Autodesk Fusion 360 part; units mm, degrees
note: some values were not read from the file. Set by a fixed rule: which face or edge a step refers to.
(part 2 of 2)
sketch "Sketch2" plane through (-9.3104, 0, 0) normal (1, 0, 0) x (0, 1, 0)
  line L0 (-29.8542, 0) -> (11.1458, 0)
  line L1 (11.1458, 0) -> (11.1458, 240)
  line L2 (11.1458, 240) -> (-29.8542, 240)
  line L3 (-29.8542, 240) -> (-29.8542, 0)
  circle A0 centre (-21.8542, 179.6) radius 2
  circle A1 centre (-21.8542, 149.6) radius 2
  circle A2 centre (-1.8542, 179.6) radius 2
  circle A3 centre (-1.8542, 149.6) radius 2
  dimension "d5" = 4
  dimension "d6" = 4
  dimension "d7" = 30
  dimension "d8" = 8
  dimension "d9" = 8
  dimension "d10" = 4
  dimension "d11" = 4
  dimension "d12" = 20
  dimension "d13" = 60.4
  dimension "d14" = 60.4
  dimension "d15" = 28
  dimension "d16" = 30
  measures "d5" diameter of A0
  measures "d6" diameter of A1
  measures "d7" vertical distance of A0.centre A1.centre
  measures "d8" distance of L3 A0.centre
  measures "d9" distance of L3 A1.centre
  measures "d10" diameter of A2
  measures "d11" diameter of A3
  measures "d12" distance of A0.centre A2.centre
  measures "d13" distance of L2 A0.centre
  measures "d14" distance of L2 A2.centre
  measures "d15" distance of L3 A3.centre
  measures "d16" distance of A2.centre A3.centre
extrude "Extrude2" cut sketch "Sketch2" against normal blind 5 contours A0 | A1 | A2 | A3
equation "d7 = 26 mm + 4 mm"
equation "d13 = 44.5 mm - 2 mm + 11.9 mm + 6 mm"
equation "d14 = d13"
equation "d15 = 8 mm + 20 mm"

design "E-box"
part number: 2026-10-19-21-22-05-736
Autodesk Fusion 360 part; units mm, degrees
sketch "Sketch1" plane through (0, 0, 0) normal (0, 0, 1) x (1, 0, 0)
  line L0 (-27.5125, 15.5989) -> (97.4875, 15.5989)
  line L1 (97.4875, 15.5989) -> (97.4875, 115.5989)
  line L2 (97.4875, 115.5989) -> (-27.5125, 115.5989)
  line L3 (-27.5125, 115.5989) -> (-27.5125, 15.5989)
  line L4 (-22.2722, 112.09) -> (92.4875, 112.09)
  line L5 (92.4875, 112.09) -> (92.4875, 20)
  line L6 (92.4875, 20) -> (-22.2722, 20)
  line L7 (-22.2722, 20) -> (-22.2722, 112.09)
  dimension "d1" = 125
  dimension "d2" = 100
  dimension "d3" = 5
  constraint horizontal L0
  constraint vertical L1
  constraint horizontal L2
  constraint vertical L3
  constraint horizontal L4
  constraint vertical L5
  constraint horizontal L6
  constraint vertical L7
  measures "d1" distance of L0.start L0.end
  measures "d2" distance of L0.start L2.end
  measures "d3" distance of L1 L5
extrude "Extrude1" add sketch "Sketch1" along normal blind 10
extrude "Extrude2" add 1 faces at (-25.7658, 50.3992, 10) along direction (0, 0, 1) blind 90
extrude "Extrude3" cut 1 faces at (-25.7658, 50.3992, 100) along direction (0, 0, -1) blind 40
sketch "Sketch2" plane through (0, 0, 0) normal (0, 0, -1) x (1, 0, 0)
  line L0 (-22.2722, -20) -> (92.4875, -20)
  line L1 (92.4875, -20) -> (92.4875, -112.09)
  line L2 (92.4875, -112.09) -> (-22.2722, -112.09)
  line L3 (-22.2722, -112.09) -> (-22.2722, -20)
  line L4 (-27.5125, -15.5989) -> (-27.5125, -115.5989)
  line L5 (-27.5125, -115.5989) -> (97.4875, -115.5989)
  line L6 (97.4875, -115.5989) -> (97.4875, -15.5989)
  line L7 (97.4875, -15.5989) -> (-27.5125, -15.5989)
  line L8 (97.4875, -74.5989) -> (-27.5125, -74.5989)
  dimension "d10" = 41
  constraint coincident L6 L8.start
  constraint coincident L4 L8.end
  constraint perpendicular L4 L8
  measures "d10" distance of L5 L8
extrude "Extrude4" cut sketch "Sketch2" against normal blind 10 contours L1 L2 L3 L4 L5 L6 L8
sketch "Sketch3" plane through (92.4875, 0, 0) normal (-1, 0, 0) x (0, -1, 0)
  line L0 (-112.09, 10) -> (-74.5989, 10)
  line L1 (-74.5989, 10) -> (-74.5989, 0)
  line L2 (-74.5989, 0) -> (-20, 0)
  line L3 (-20, 0) -> (-20, 60)
  line L4 (-20, 60) -> (-112.09, 60)
  line L5 (-112.09, 60) -> (-112.09, 10)
  line L6 (-74.5989, 5) -> (-20, 5)
  constraint midpoint L1 L6.start
  constraint coincident L3 L6.end
  constraint perpendicular L3 L6
extrude "Extrude5" add sketch "Sketch3" along normal blind 115 contours L1 L2 L3 L6
sketch "Sketch4" plane through (0, 0, 60) normal (0, 0, 1) x (-1, 0, 0)
  line L0 (-92.4875, -20) -> (22.2722, -20)
  line L1 (22.2722, -20) -> (22.2722, -112.09)
  line L2 (22.2722, -112.09) -> (-92.4875, -112.09)
  line L3 (-92.4875, -112.09) -> (-92.4875, -20)
  line L4 (27.5125, -115.5989) -> (27.5125, -15.5989)
  line L5 (27.5125, -15.5989) -> (-97.4875, -15.5989)
  line L6 (-97.4875, -15.5989) -> (-97.4875, -115.5989)
  line L7 (-97.4875, -115.5989) -> (27.5125, -115.5989)
  line L8 (22.2722, -20) -> (27.5125, -20)
  line L9 (22.2722, -112.09) -> (27.5125, -112.09)
  constraint coincident L0.end L1.start
  constraint coincident L4 L8.end
  constraint perpendicular L4 L8
  constraint coincident L1.end L2.start
  constraint coincident L4 L9.end
  constraint perpendicular L4 L9
extrude "Extrude6" cut sketch "Sketch4" against normal blind 7 contours L1 L4 L8 L9
sketch "Sketch5" plane through (0, 20, 0) normal (0, 1, 0) x (-1, 0, 0)
  line L0 (-92.4875, 5) -> (22.2722, 5)
  line L1 (22.2722, 5) -> (22.2722, 53)
  line L2 (22.2722, 53) -> (27.5125, 53)
  line L3 (27.5125, 53) -> (27.5125, 60)
  line L4 (27.5125, 60) -> (-92.4875, 60)
  line L5 (-92.4875, 60) -> (-92.4875, 5)
  line L6 (-92.4875, 60) -> (24.7074, 60)
  line L7 (24.7074, 60) -> (24.7074, 57)
  line L8 (24.7074, 57) -> (-92.4875, 57)
  line L9 (-92.4875, 57) -> (-92.4875, 60)
  dimension "d17" = 3
  constraint horizontal L6
  constraint vertical L7
  constraint horizontal L8
  constraint vertical L9
  constraint coincident L4.end L5.start
  measures "d17" distance of L4.end L8.end
extrude "Extrude7" add sketch "Sketch5" along normal blind 2 contours L4 L5 L6 L7 L8 L9
sketch "Sketch6" plane through (0, 112.09, 0) normal (0, -1, 0) x (1, 0, 0)
  line L0 (-22.2722, 10) -> (92.4875, 10)
  line L1 (92.4875, 10) -> (92.4875, 60)
  line L2 (92.4875, 60) -> (-27.5125, 60)
  line L3 (-27.5125, 60) -> (-27.5125, 53)
  line L4 (-27.5125, 53) -> (-22.2722, 53)
  line L5 (-22.2722, 53) -> (-22.2722, 10)
  line L6 (-27.5125, 60) -> (92.4875, 60)
  line L7 (92.4875, 60) -> (92.4875, 57)
  line L8 (92.4875, 57) -> (-27.5125, 57)
  line L9 (-27.5125, 57) -> (-27.5125, 60)
  dimension "d20" = 3
  constraint horizontal L6
  constraint vertical L7
  constraint horizontal L8
  constraint vertical L9
  constraint coincident L2.end L3.start
  measures "d20" distance of L2.end L8.end
extrude "Extrude8" add sketch "Sketch6" along normal blind 2 contours L1 L2 L3 L6 L7 L8 L9
sketch "Sketch7" plane through (0, 112.09, 0) normal (0, -1, 0) x (1, 0, 0)
  line L0 (92.4875, 57) -> (-27.5125, 57)
  line L1 (-27.5125, 57) -> (-27.5125, 53)
  line L2 (-27.5125, 53) -> (-22.2722, 53)
  line L3 (-22.2722, 53) -> (-22.2722, 10)
  line L4 (-22.2722, 10) -> (92.4875, 10)
  line L5 (92.4875, 10) -> (92.4875, 57)
  line L6 (-22.2722, 53) -> (92.4875, 53)
  line L7 (92.4875, 53) -> (92.4875, 51)
  line L8 (92.4875, 51) -> (-22.2722, 51)
  line L9 (-22.2722, 51) -> (-22.2722, 53)
  dimension "d23" = 2
  constraint horizontal L6
  constraint vertical L7
  constraint horizontal L8
  constraint vertical L9
  constraint coincident L2.end L3.start
  measures "d23" distance of L2.end L8.end
extrude "Extrude9" add sketch "Sketch7" along normal blind 2 contours L3 L5 L6 L7 L8 L9
sketch "Sketch8" plane through (0, 20, 0) normal (0, 1, 0) x (-1, 0, 0)
  line L0 (24.7074, 60) -> (24.7074, 57)
  line L1 (24.7074, 57) -> (-92.4875, 57)
  line L2 (-92.4875, 57) -> (-92.4875, 5)
  line L3 (-92.4875, 5) -> (22.2722, 5)
  line L4 (22.2722, 5) -> (22.2722, 53)
  line L5 (22.2722, 53) -> (27.5125, 53)
  line L6 (27.5125, 53) -> (27.5125, 60)
  line L7 (27.5125, 60) -> (24.7074, 60)
  line L8 (22.2722, 53) -> (-92.4875, 53)
  line L9 (-92.4875, 53) -> (-92.4875, 51)
  line L10 (-92.4875, 51) -> (22.2722, 51)
  line L11 (22.2722, 51) -> (22.2722, 53)
  dimension "d26" = 2
  constraint horizontal L8
  constraint vertical L9
  constraint horizontal L10
  constraint vertical L11
  constraint coincident L4.end L5.start
  measures "d26" distance of L4.end L10.end
extrude "Extrude10" add sketch "Sketch8" along normal blind 2 contours L2 L4 L8 L9 L10 L11
sketch "Sketch9" plane through (0, 0, 53) normal (0, 0, 1) x (-1, 0, 0)
  line L0 (-92.4875, -112.09) -> (27.5125, -112.09)
  line L1 (27.5125, -112.09) -> (27.5125, -20)
  line L2 (27.5125, -20) -> (-92.4875, -20)
  line L3 (-92.4875, -20) -> (-92.4875, -22)
  line L4 (-92.4875, -22) -> (22.2722, -22)
  line L5 (22.2722, -22) -> (22.2722, -110.09)
  line L6 (22.2722, -110.09) -> (-92.4875, -110.09)
  line L7 (-92.4875, -110.09) -> (-92.4875, -112.09)
  line L8 (27.5125, -20) -> (22.2722, -20)
  line L9 (22.2722, -20) -> (22.2722, -112.09)
  line L10 (22.2722, -112.09) -> (27.5125, -112.09)
  line L11 (27.5125, -112.09) -> (27.5125, -20)
  constraint horizontal L8
  constraint vertical L9
  constraint horizontal L10
  constraint vertical L11
  constraint coincident L0 L9.end
  constraint coincident L1.end L2.start
extrude "Extrude11" add sketch "Sketch9" along normal blind 7 contours L0 L1 L2 L5 L8 L9 L10 L11
sketch "Sketch10" plane through (0, 0, 60) normal (0, 0, 1) x (-1, 0, 0)
  line L0 (22.2722, -110.09) -> (-92.4875, -110.09)
  line L1 (-92.4875, -110.09) -> (-92.4875, -22)
  line L2 (-92.4875, -22) -> (22.2722, -22)
  line L3 (22.2722, -22) -> (22.2722, -110.09)
  line L4 (27.5125, -115.5989) -> (27.5125, -15.5989)
  line L5 (27.5125, -15.5989) -> (-97.4875, -15.5989)
  line L6 (-97.4875, -15.5989) -> (-97.4875, -115.5989)
  line L7 (-97.4875, -115.5989) -> (27.5125, -115.5989)
  line L8 (-92.4875, -110.09) -> (-97.4875, -110.09)
  line L9 (-97.4875, -110.09) -> (-97.4875, -22)
  line L10 (-97.4875, -22) -> (-92.4875, -22)
  line L11 (-92.4875, -22) -> (-92.4875, -110.09)
  constraint horizontal L8
  constraint vertical L9
  constraint horizontal L10
  constraint vertical L11
  constraint coincident L6 L9.end
  constraint coincident L0.end L1.start
extrude "Extrude12" cut sketch "Sketch10" against normal blind 7 contours L1 L6 L8 L9 L10 L11
extrude "Extrude13" cut 1 faces at (92.4875, 111.4234, 54.3333) along direction (1, 0, 0) blind 20
extrude "Extrude14" cut 1 faces at (92.4875, 21.3333, 54.3333) along direction (1, 0, 0) blind 40
fillet "Fillet1" radius 2 3 edges at (34.9875, 15.5989, 60) (-27.5125, 65.5989, 60) (34.9875, 115.5989, 60)
fillet "Fillet2" radius 2 10 edges at (97.4875, 15.5989, 29) (97.4875, 16.1846, 59.4142) (97.4875, 19.7994, 60) (-27.5125, 15.5989, 29) (-26.9267, 16.1846, 59.4142) (-27.5125, 115.5989, 34) (-26.9267, 115.0131, 59.4142) (97.4875, 115.5989, 34) (97.4875, 115.0131, 59.4142) (97.4875, 111.8444, 60)
sketch "Sketch11" plane through (0, 20, 0) normal (0, 1, 0) x (-1, 0, 0)
  line L0 (22.2722, 51) -> (-92.4875, 51)
  line L1 (-92.4875, 51) -> (-92.4875, 5)
  line L2 (-92.4875, 5) -> (22.2722, 5)
  line L3 (22.2722, 5) -> (22.2722, 51)
  line L4 (13.7722, 5) -> (3.7722, 5)
  line L5 (3.7722, 5) -> (3.7722, 10)
  line L6 (3.7722, 10) -> (13.7722, 10)
  line L7 (13.7722, 10) -> (13.7722, 5)
  dimension "d41" = 10
  dimension "d42" = 5
  dimension "d43" = 8.5
  constraint horizontal L4
  constraint vertical L5
  constraint horizontal L6
  constraint vertical L7
  constraint coincident L2 L4.start
  measures "d41" distance of L4.start L4.end
  measures "d42" distance of L4.start L6.end
  measures "d43" distance of L3 L7
extrude "Extrude15" cut sketch "Sketch11" against normal blind 19 contours L2 L4 L5 L6 L7

design "Rod Holder (Front Part)"
part number: 2026-10-13-13-00-43-500
Autodesk Fusion 360 part; units mm, degrees
sketch "Sketch1" plane through (0, 0, 0) normal (0, 0, 1) x (1, 0, 0)
  line L0 (-14.2666, 6.6875) -> (165.7334, 6.6875)
  line L1 (165.7334, 6.6875) -> (165.7334, -13.3125)
  line L2 (165.7334, -13.3125) -> (-14.2666, -13.3125)
  line L3 (-14.2666, -13.3125) -> (-14.2666, 6.6875)
  dimension "d1" = 180
  dimension "d2" = 20
  constraint horizontal L0
  constraint vertical L1
  constraint horizontal L2
  constraint vertical L3
  measures "d1" distance of L0.start L0.end
  measures "d2" distance of L0.start L2.end
extrude "Extrude1" add sketch "Sketch1" along normal blind 55
sketch "Sketch2" plane through (0, 6.6875, 0) normal (0, 1, 0) x (-1, 0, 0)
  line L0 (-165.7334, 0) -> (14.2666, 0)
  line L1 (14.2666, 0) -> (14.2666, 55)
  line L2 (14.2666, 55) -> (-165.7334, 55)
  line L3 (-165.7334, 55) -> (-165.7334, 0)
  line L4 (-85.2334, 55) -> (-66.2334, 55)
  line L5 (-66.2334, 55) -> (-66.2334, 0)
  line L6 (-66.2334, 0) -> (-85.2334, 0)
  line L7 (-85.2334, 0) -> (-85.2334, 55)
  dimension "d5" = 19
  dimension "d6" = 80.5
  dimension "d7" = 80.5
  constraint horizontal L4
  constraint vertical L5
  constraint horizontal L6
  constraint vertical L7
  constraint coincident L2 L4.start
  measures "d5" distance of L4.start L4.end
  measures "d6" distance of L1 L5
  measures "d7" distance of L3 L7
extrude "Extrude2" cut sketch "Sketch2" against normal blind 5 contours L0 L2 L4 L5 L6 L7
sketch "Sketch3" plane through (0, 6.6875, 0) normal (0, 1, 0) x (-1, 0, 0)
  line L0 (-66.2334, 55) -> (-66.2334, 0)
  line L1 (-66.2334, 0) -> (14.2666, 0)
  line L2 (14.2666, 0) -> (14.2666, 55)
  line L3 (14.2666, 55) -> (-66.2334, 55)
  circle A0 centre (-21.7334, 43) radius 4
  dimension "d10" = 8
  dimension "d11" = 43
  dimension "d12" = 36
  measures "d10" diameter of A0
  measures "d11" distance of L1 A0.centre
  measures "d12" distance of L2 A0.centre
extrude "Extrude3" cut sketch "Sketch3" against normal blind 100 contours A0
sketch "Sketch4" plane through (0, 6.6875, 0) normal (0, 1, 0) x (-1, 0, 0)
  line L0 (-85.2334, 0) -> (-85.2334, 55)
  line L1 (-85.2334, 55) -> (-165.7334, 55)
  line L2 (-165.7334, 55) -> (-165.7334, 0)
  line L3 (-165.7334, 0) -> (-85.2334, 0)
  circle A0 centre (-129.7334, 43) radius 4
  dimension "d15" = 8
  dimension "d16" = 43
  dimension "d17" = 36
  measures "d15" diameter of A0
  measures "d16" distance of L3 A0.centre
  measures "d17" distance of L2 A0.centre
extrude "Extrude4" cut sketch "Sketch4" against normal blind 20 contours A0
fillet "Fillet1" chord length 10 1 edges at (165.7334, -3.3125, 55)
fillet "Fillet2" chord length 10 1 edges at (-14.2666, -3.3125, 55)
sketch "Sketch5" plane through (0, 1.6875, 0) normal (0, 1, 0) x (-1, 0, 0)
  line L0 (-85.2334, 0) -> (-66.2334, 0)
  line L1 (-66.2334, 0) -> (-66.2334, 55)
  line L2 (-66.2334, 55) -> (-85.2334, 55)
  line L3 (-85.2334, 55) -> (-85.2334, 0)
  line L4 (-85.2334, 55) -> (-66.2334, 55)
  line L5 (-66.2334, 55) -> (-66.2334, 41)
  line L6 (-66.2334, 41) -> (-85.2334, 41)
  line L7 (-85.2334, 41) -> (-85.2334, 55)
  dimension "d24" = 14
  constraint horizontal L4
  constraint vertical L5
  constraint horizontal L6
  constraint vertical L7
  constraint coincident L2.end L3.start
  measures "d24" distance of L2.end L6.end
extrude "Extrude5" add sketch "Sketch5" along normal blind 5 contours L1 L2 L3 L4 L5 L6 L7
sketch "Sketch6" plane through (0, 0, 55) normal (0, 0, 1) x (-1, 0, 0)
  line L0 (7.1956, 13.3125) -> (7.1956, -6.6875)
  line L1 (7.1956, 13.3125) -> (-158.6623, 13.3125)
  line L2 (-158.6623, -6.6875) -> (-158.6623, 13.3125)
  line L3 (-158.6623, -6.6875) -> (7.1956, -6.6875)
  line L4 (-67.8201, 2.2173) -> (-37.8201, 2.2173)
  line L5 (-37.8201, 2.2173) -> (-37.8201, 10.4173)
  line L6 (-37.8201, 10.4173) -> (-67.8201, 10.4173)
  line L7 (-67.8201, 10.4173) -> (-67.8201, 2.2173)
  dimension "d27" = 30
  dimension "d28" = 8.2
  constraint horizontal L4
  constraint vertical L5
  constraint horizontal L6
  constraint vertical L7
  measures "d27" distance of L4.start L4.end
  measures "d28" distance of L4.start L6.end
extrude "Extrude6" cut sketch "Sketch6" against normal blind 30 contours L4 L5 L6 L7
sketch "Sketch7" plane through (0, 6.6875, 0) normal (0, 1, 0) x (-1, 0, 0)
  circle A0 centre (-21.7334, 43) radius 4
  spline S0 degree 3 poles (-165.7334, 47.9289) (-165.7334, 48.8626) (-165.5484, 49.7871) (-164.8258, 51.5212) (-164.2911, 52.3119) (-162.9686, 53.6106) (-162.2037, 54.1163) (-160.5074, 54.8177) (-159.5893, 55) (-158.6623, 55) knots 0 0 0 0 0.280098 0.280098 0.563604 0.563604 0.836161 0.836161 1.114279 1.114279 1.114279 1.114279
  line L0 (-165.7334, 47.9289) -> (-165.7334, 0)
  line L1 (-165.7334, 0) -> (-85.2334, 0)
  line L2 (-85.2334, 0) -> (-85.2334, 41)
  line L3 (-85.2334, 41) -> (-66.2334, 41)
  line L4 (-66.2334, 41) -> (-66.2334, 0)
  line L5 (-66.2334, 0) -> (14.2666, 0)
  line L6 (14.2666, 0) -> (14.2666, 47.9289)
  spline S1 degree 3 poles (7.1956, 55) (8.1292, 55) (9.0537, 54.8151) (10.7879, 54.0924) (11.5785, 53.5577) (12.8772, 52.2352) (13.383, 51.4704) (14.0843, 49.7741) (14.2666, 48.856) (14.2666, 47.9289) knots 0 0 0 0 0.280098 0.280098 0.563604 0.563604 0.836161 0.836161 1.114279 1.114279 1.114279 1.114279
  line L7 (7.1956, 55) -> (-158.6623, 55)
  circle A1 centre (-129.7334, 43) radius 4
  line L8 (-65.7334, 37) -> (-45.7334, 37)
  line L9 (-45.7334, 37) -> (-45.7334, 25)
  line L10 (-45.7334, 25) -> (-65.7334, 25)
  line L11 (-65.7334, 25) -> (-65.7334, 37)
  dimension "d33" = 12
  dimension "d54" = 0.5
  constraint horizontal L8
  constraint vertical L9
  constraint horizontal L10
  constraint vertical L11
  measures "d33" distance of L8 L10
  measures "d54" distance of L4 L11
extrude "Extrude7" cut sketch "Sketch7" against normal blind 25 contours L8 L9 L10 L11
sketch "Sketch8" plane through (0, 0, 25) normal (0, 0, 1) x (-1, 0, 0)
  line L0 (-65.7334, 10.4173) -> (-67.8201, 10.4173)
  line L1 (-67.8201, 10.4173) -> (-67.8201, 2.2173)
  line L2 (-67.8201, 2.2173) -> (-65.7334, 2.2173)
  line L3 (-65.7334, 2.2173) -> (-65.7334, -6.6875)
  line L4 (-65.7334, -6.6875) -> (-45.7334, -6.6875)
  line L5 (-45.7334, -6.6875) -> (-45.7334, 2.2173)
  line L6 (-45.7334, 2.2173) -> (-37.8201, 2.2173)
  line L7 (-37.8201, 2.2173) -> (-37.8201, 10.4173)
  line L8 (-37.8201, 10.4173) -> (-45.7334, 10.4173)
  line L9 (-45.7334, 10.4173) -> (-45.7334, 13.3125)
  line L10 (-45.7334, 13.3125) -> (-65.7334, 13.3125)
  line L11 (-65.7334, 13.3125) -> (-65.7334, 10.4173)
  line L12 (-67.8201, 2.2173) -> (-65.7334, 2.2173)
  line L13 (-65.7334, 2.2173) -> (-65.7334, 10.4173)
  line L14 (-65.7334, 10.4173) -> (-67.8201, 10.4173)
  line L15 (-67.8201, 10.4173) -> (-67.8201, 2.2173)
  line L16 (-37.8201, 10.4173) -> (-45.7334, 10.4173)
  line L17 (-45.7334, 10.4173) -> (-45.7334, 2.2173)
  line L18 (-45.7334, 2.2173) -> (-37.8201, 2.2173)
  line L19 (-37.8201, 2.2173) -> (-37.8201, 10.4173)
  constraint horizontal L12
  constraint vertical L13
  constraint horizontal L14
  constraint vertical L15
  constraint coincident L0.start L11.end
  constraint coincident L1.end L2.start
  constraint horizontal L16
  constraint vertical L17
  constraint horizontal L18
  constraint vertical L19
  constraint coincident L5.end L6.start
  constraint coincident L7.end L8.start
extrude "Extrude8" add sketch "Sketch8" along normal blind 5 contours L0 L1 L2 L12 L13 L14 L15 | L6 L7 L8 L16 L17 L18 L19
sketch "Sketch9" plane through (65.7334, 0, 0) normal (-1, 0, 0) x (0, -1, 0)
  line L0 (-6.6875, 25) -> (13.3125, 25)
  line L1 (13.3125, 25) -> (13.3125, 37)
  line L2 (13.3125, 37) -> (10.4173, 37)
  line L3 (10.4173, 37) -> (10.4173, 30)
  line L4 (10.4173, 30) -> (2.2173, 30)
  line L5 (2.2173, 30) -> (2.2173, 37)
  line L6 (2.2173, 37) -> (-6.6875, 37)
  line L7 (-6.6875, 37) -> (-6.6875, 25)
  circle A0 centre (6.3173, 32.4309) radius 4
  dimension "d36" = 8
  measures "d36" diameter of A0
extrude "Extrude9" cut sketch "Sketch9" against normal blind 7.82 contours L4 A0 picked at (7.2516, 29.8591)
extrude "Extrude10" cut sketch "Sketch9" against normal blind 7.82 contours L4 A0 picked at (7.2516, 29.8591)
extrude "Extrude11" cut sketch "Sketch9" along normal blind 22.18 contours L4 A0 picked at (7.2516, 29.8591)
sketch "Sketch10" plane through (0, 6.6875, 0) normal (0, 1, 0) x (-1, 0, 0)
  line L0 (-45.7334, 37) -> (-45.7334, 25)
  line L1 (-45.7334, 25) -> (-65.7334, 25)
  line L2 (-65.7334, 25) -> (-65.7334, 37)
  line L3 (-65.7334, 37) -> (-45.7334, 37)
  circle A0 centre (-21.7334, 43) radius 4
  spline S0 degree 3 poles (-165.7334, 47.9289) (-165.7334, 48.8626) (-165.5484, 49.7871) (-164.8258, 51.5212) (-164.2911, 52.3119) (-162.9686, 53.6106) (-162.2037, 54.1163) (-160.5074, 54.8177) (-159.5893, 55) (-158.6623, 55) knots 0 0 0 0 0.280098 0.280098 0.563604 0.563604 0.836161 0.836161 1.114279 1.114279 1.114279 1.114279
  line L4 (-165.7334, 47.9289) -> (-165.7334, 0)
  line L5 (-165.7334, 0) -> (-85.2334, 0)
  line L6 (-85.2334, 0) -> (-85.2334, 41)
  line L7 (-85.2334, 41) -> (-66.2334, 41)
  line L8 (-66.2334, 41) -> (-66.2334, 0)
  line L9 (-66.2334, 0) -> (14.2666, 0)
  line L10 (14.2666, 0) -> (14.2666, 47.9289)
  spline S1 degree 3 poles (7.1956, 55) (8.1292, 55) (9.0537, 54.8151) (10.7879, 54.0924) (11.5785, 53.5577) (12.8772, 52.2352) (13.383, 51.4704) (14.0843, 49.7741) (14.2666, 48.856) (14.2666, 47.9289) knots 0 0 0 0 0.280098 0.280098 0.563604 0.563604 0.836161 0.836161 1.114279 1.114279 1.114279 1.114279
  line L11 (7.1956, 55) -> (-158.6623, 55)
  circle A1 centre (-129.7334, 43) radius 4
  line L12 (-65.7334, 37) -> (-40, 37)
  line L13 (-40, 37) -> (-40, 42)
  line L14 (-40, 42) -> (-65.7334, 42)
  line L15 (-65.7334, 42) -> (-65.7334, 37)
  constraint horizontal L12
  constraint vertical L13
  constraint horizontal L14
  constraint vertical L15
  constraint coincident L2.end L3.start
extrude "Extrude12" cut sketch "Sketch10" against normal blind 11 contours L3 L12 L13 L14 L15
sketch "Sketch11" plane through (0, 0, 25) normal (0, 0, 1) x (-1, 0, 0)
  line L0 (-65.7334, 13.3125) -> (-65.7334, -6.6875)
  line L1 (-65.7334, -6.6875) -> (-45.7334, -6.6875)
  line L2 (-45.7334, -6.6875) -> (-45.7334, 13.3125)
  line L3 (-45.7334, 13.3125) -> (-65.7334, 13.3125)
  line L4 (-65.7334, 0.7071) -> (-45.7334, 0.7071)
  line L5 (-45.7334, 0.7071) -> (-45.7334, -6.6875)
  line L6 (-45.7334, -6.6875) -> (-65.7334, -6.6875)
  line L7 (-65.7334, -6.6875) -> (-65.7334, 0.7071)
  constraint horizontal L4
  constraint vertical L5
  constraint horizontal L6
  constraint vertical L7
  constraint coincident L1.end L2.start
  constraint coincident L0 L4.start
extrude "Extrude13" add sketch "Sketch11" along normal blind 2 contours L0 L1 L2 L4 L5 L6 L7
chamfer "Chamfer1" distance 5 angle 45 1 edges at (65.7334, 2.2351, 42) tangent chain off
chamfer "Chamfer2" distance 5 angle 45 1 edges at (40, 2.2351, 42) tangent chain off
fillet "Fillet3" radius 1.5 1 edges at (65.7334, 2.9902, 27)
fillet "Fillet4" radius 1.5 1 edges at (45.7334, 2.9902, 27)
sketch "Sketch12" plane through (0, 6.6875, 0) normal (0, 1, 0) x (-1, 0, 0)
  line L0 (-40, 37) -> (-45.7334, 37)
  line L1 (-45.7334, 37) -> (-45.7334, 28.5)
  arc A0 (-47.2334, 27) -> (-45.7334, 28.5) centre (-47.2334, 28.5) ccw
  line L2 (-47.2334, 27) -> (-64.2334, 27)
  arc A1 (-65.7334, 28.5) -> (-64.2334, 27) centre (-64.2334, 28.5) ccw
  line L3 (-65.7334, 28.5) -> (-65.7334, 37)
  line L4 (-65.7334, 37) -> (-60.7334, 42)
  line L5 (-60.7334, 42) -> (-45, 42)
  line L6 (-45, 42) -> (-40, 37)
  circle A2 centre (-21.7334, 43) radius 4
  spline S0 degree 3 poles (-165.7334, 47.9289) (-165.7334, 48.8626) (-165.5484, 49.7871) (-164.8258, 51.5212) (-164.2911, 52.3119) (-162.9686, 53.6106) (-162.2037, 54.1163) (-160.5074, 54.8177) (-159.5893, 55) (-158.6623, 55) knots 0 0 0 0 0.280098 0.280098 0.563604 0.563604 0.836161 0.836161 1.114279 1.114279 1.114279 1.114279
  line L7 (-165.7334, 47.9289) -> (-165.7334, 0)
  line L8 (-165.7334, 0) -> (-85.2334, 0)
  line L9 (-85.2334, 0) -> (-85.2334, 41)
  line L10 (-85.2334, 41) -> (-66.2334, 41)
  line L11 (-66.2334, 41) -> (-66.2334, 0)
  line L12 (-66.2334, 0) -> (14.2666, 0)
  line L13 (14.2666, 0) -> (14.2666, 47.9289)
  spline S1 degree 3 poles (7.1956, 55) (8.1292, 55) (9.0537, 54.8151) (10.7879, 54.0924) (11.5785, 53.5577) (12.8772, 52.2352) (13.383, 51.4704) (14.0843, 49.7741) (14.2666, 48.856) (14.2666, 47.9289) knots 0 0 0 0 0.280098 0.280098 0.563604 0.563604 0.836161 0.836161 1.114279 1.114279 1.114279 1.114279
  line L14 (7.1956, 55) -> (-158.6623, 55)
  circle A3 centre (-129.7334, 43) radius 4
  line L15 (-40, 37) -> (-40, 27)
  line L16 (-40, 27) -> (-49, 27)
  constraint coincident L0.start L6.end
  constraint perpendicular L0 L15
  constraint coincident L2 L16.end
extrude "Extrude14" cut sketch "Sketch12" against normal blind 9 contours L0 L1 A0 L15 L16
extrude "Extrude15" add 1 faces at (37.8201, -4.9506, 38.3333) along direction (1, 0, 0) blind 5
extrude "Extrude16" add 1 faces at (40, 3.7192, 31.3333) along direction (1, 0, 0) blind 2.82
extrude "Extrude17" add 1 faces at (41.88, 3.7192, 37) along direction (0, 0, 1) blind 4
sketch "Sketch13" plane through (0, 6.6875, 0) normal (0, 1, 0) x (-1, 0, 0)
  circle A0 centre (-129.7334, 43) radius 4
  spline S0 degree 3 poles (-165.7334, 47.9289) (-165.7334, 48.8626) (-165.5484, 49.7871) (-164.8258, 51.5212) (-164.2911, 52.3119) (-162.9686, 53.6106) (-162.2037, 54.1163) (-160.5074, 54.8177) (-159.5893, 55) (-158.6623, 55) knots 0 0 0 0 0.280098 0.280098 0.563604 0.563604 0.836161 0.836161 1.114279 1.114279 1.114279 1.114279
  line L0 (-165.7334, 47.9289) -> (-165.7334, 0)
  line L1 (-165.7334, 0) -> (-85.2334, 0)
  line L2 (-85.2334, 0) -> (-85.2334, 41)
  line L3 (-85.2334, 41) -> (-66.2334, 41)
  line L4 (-66.2334, 41) -> (-66.2334, 0)
  line L5 (-66.2334, 0) -> (14.2666, 0)
  line L6 (14.2666, 0) -> (14.2666, 47.9289)
  spline S1 degree 3 poles (7.1956, 55) (8.1292, 55) (9.0537, 54.8151) (10.7879, 54.0924) (11.5785, 53.5577) (12.8772, 52.2352) (13.383, 51.4704) (14.0843, 49.7741) (14.2666, 48.856) (14.2666, 47.9289) knots 0 0 0 0 0.280098 0.280098 0.563604 0.563604 0.836161 0.836161 1.114279 1.114279 1.114279 1.114279
  line L7 (7.1956, 55) -> (-158.6623, 55)
  circle A1 centre (-21.7334, 43) radius 4
  line L8 (-42.82, 39.82) -> (-42.82, 27)
  line L9 (-42.82, 27) -> (-64.2334, 27)
  arc A2 (-65.7334, 28.5) -> (-64.2334, 27) centre (-64.2334, 28.5) ccw
  line L10 (-65.7334, 28.5) -> (-65.7334, 37)
  line L11 (-65.7334, 37) -> (-60.7334, 42)
  line L12 (-60.7334, 42) -> (-45, 42)
  line L13 (-45, 42) -> (-42.82, 39.82)
  line L14 (-60.7334, 42) -> (-43, 42)
  line L15 (-43, 42) -> (-42.82, 27)
  line L16 (-42.82, 27) -> (-65.7334, 27)
  line L17 (-65.7334, 27) -> (-65.7334, 42)
  line L18 (-65.7334, 42) -> (-59, 42)
  constraint coincident L11.end L12.start
  constraint parallel L12 L14
  constraint coincident L8.end L9.start
  constraint perpendicular L3 L17
  constraint coincident L14 L18.end
  constraint perpendicular L17 L18
extrude "Extrude18" cut sketch "Sketch13" against normal blind 9 contours L13 L14 L15 | L11 L17 L18
chamfer "Chamfer3" distance 2 angle 45 2 edges at (43, 2.2351, 42) (65.7334, 2.2351, 42) tangent chain off
fillet "Fillet5" radius 4.5 1 edges at (42.82, 2.1875, 27)
sketch "Sketch14" plane through (0, 0, 55) normal (0, 0, 1) x (-1, 0, 0)
  line L0 (-42.8201, 2.2173) -> (-67.8201, 2.2173)
  line L1 (-67.8201, 2.2173) -> (-67.8201, 10.4173)
  line L2 (-67.8201, 10.4173) -> (-42.8201, 10.4173)
  line L3 (-42.8201, 10.4173) -> (-42.8201, 2.2173)
  line L4 (7.1956, 13.3125) -> (7.1956, -6.6875)
  line L5 (7.1956, 13.3125) -> (-158.6623, 13.3125)
  line L6 (-158.6623, -6.6875) -> (-158.6623, 13.3125)
  line L7 (-158.6623, -6.6875) -> (7.1956, -6.6875)
  circle A0 centre (-106.2123, 2.2982) radius 1.95
  circle A1 centre (-5.9306, 1.6911) radius 1.95
  dimension "d68" = 3.9
  dimension "d69" = 3.9
  measures "d68" diameter of A0
  measures "d69" diameter of A1
extrude "Extrude19" cut sketch "Sketch14" against normal blind 85 contours A0 | A1
equation "d11 = 4 mm + 35 mm + 4 mm"
equation "d12 = 32 mm + 4 mm"
equation "d16 = 39 mm + 4 mm"
equation "d17 = 32 mm + 4 mm"

design "Y_Moving Part"
part number: 2026-10-14-18-31-05-865
Autodesk Fusion 360 part; units mm, degrees
sketch "Sketch1" plane through (0, 0, 0) normal (0, 0, 1) x (1, 0, 0)
  line L0 (-22.9604, 18.0562) -> (29.0396, 18.0562)
  line L1 (29.0396, 18.0562) -> (29.0396, -41.9438)
  line L2 (29.0396, -41.9438) -> (-22.9604, -41.9438)
  line L3 (-22.9604, -41.9438) -> (-22.9604, 18.0562)
  circle A0 centre (17.0396, -26.9438) radius 7.5
  circle A1 centre (-2.9604, 3.0562) radius 7.5
  dimension "d1" = 52
  dimension "d2" = 60
  dimension "d9" = 15
  dimension "d10" = 15
  dimension "d11" = 15
  dimension "d12" = 15
  dimension "d13" = 20
  dimension "d14" = 40
  constraint horizontal L0
  constraint vertical L1
  constraint horizontal L2
  constraint vertical L3
  measures "d1" distance of L0.start L0.end
  measures "d2" distance of L0.start L2.end
  measures "d9" diameter of A0
  measures "d10" diameter of A1
  measures "d11" distance of L2 A0.centre
  measures "d12" distance of L0 A1.centre
  measures "d13" distance of L3 A1.centre
  measures "d14" distance of L3 A0.centre
extrude "Extrude1" add sketch "Sketch1" along normal blind 53
sketch "Sketch3" plane through (0, 0, 53) normal (0, 0, 1) x (-1, 0, 0)
  circle A0 centre (2.9604, -3.0562) radius 7.5
  circle A1 centre (-17.0396, 26.9438) radius 7.5
  line L0 (22.9604, 41.9438) -> (-29.0396, 41.9438)
  line L1 (-29.0396, 41.9438) -> (-29.0396, -18.0562)
  line L2 (-29.0396, -18.0562) -> (22.9604, -18.0562)
  line L3 (22.9604, -18.0562) -> (22.9604, 41.9438)
  circle A2 centre (-8.9896, 8.8938) radius 5
  dimension "d17" = 10
  dimension "d18" = 33.05
  dimension "d19" = 31.95
  measures "d17" diameter of A2
  measures "d18" distance of L0 A2.centre
  measures "d19" distance of L3 A2.centre
extrude "Extrude2" cut sketch "Sketch3" against normal blind 110 contours A2
sketch "Sketch4" plane through (-22.9604, 0, 0) normal (-1, 0, 0) x (0, -1, 0)
  line L0 (-18.0562, 0) -> (41.9438, 0)
  line L1 (41.9438, 0) -> (41.9438, 53)
  line L2 (41.9438, 53) -> (-18.0562, 53)
  line L3 (-18.0562, 53) -> (-18.0562, 0)
  circle A0 centre (26.9438, 43) radius 4
  circle A1 centre (26.9438, 13) radius 4
  dimension "d22" = 8
  dimension "d23" = 8
  dimension "d24" = 30
  dimension "d25" = 15
  dimension "d26" = 15
  dimension "d27" = 10
  measures "d22" diameter of A0
  measures "d23" diameter of A1
  measures "d24" vertical distance of A0.centre A1.centre
  measures "d25" distance of L1 A1.centre
  measures "d26" distance of L1 A0.centre
  measures "d27" distance of L2 A0.centre
extrude "Extrude3" cut sketch "Sketch4" against normal blind 35 contours A0 | A1
sketch "Sketch5" plane through (0, -41.9438, 0) normal (0, -1, 0) x (1, 0, 0)
  line L0 (-22.9604, 0) -> (29.0396, 0)
  line L1 (29.0396, 0) -> (29.0396, 53)
  line L2 (29.0396, 53) -> (-22.9604, 53)
  line L3 (-22.9604, 53) -> (-22.9604, 0)
  circle A0 centre (-8.6132, 28.3474) radius 11
  dimension "d30" = 22
  measures "d30" diameter of A0
extrude "Extrude4" cut sketch "Sketch5" against normal blind 23 contours A0
sketch "Sketch6" plane through (-22.9604, 0, 0) normal (-1, 0, 0) x (0, -1, 0)
  circle A0 centre (26.9438, 43) radius 4
  circle A1 centre (26.9438, 13) radius 4
  line L0 (-18.0562, 0) -> (41.9438, 0)
  line L1 (41.9438, 0) -> (41.9438, 53)
  line L2 (41.9438, 53) -> (-18.0562, 53)
  line L3 (-18.0562, 53) -> (-18.0562, 0)
  line L4 (21, 32) -> (37.224, 32)
  line L5 (37.224, 32) -> (37.224, 23)
  line L6 (37.224, 23) -> (21, 23)
  line L7 (21, 23) -> (21, 32)
  constraint horizontal L4
  constraint vertical L5
  constraint horizontal L6
  constraint vertical L7
extrude "Extrude5" cut sketch "Sketch6" against normal blind 10 contours L4 L5 L6 L7
sketch "Sketch7" plane through (0, -41.9438, 0) normal (0, -1, 0) x (1, 0, 0)
  circle A0 centre (-8.6132, 28.3474) radius 11
  line L0 (-22.9604, 0) -> (29.0396, 0)
  line L1 (29.0396, 0) -> (29.0396, 53)
  line L2 (29.0396, 53) -> (-22.9604, 53)
  line L3 (-22.9604, 53) -> (-22.9604, 0)
  line L4 (14.9606, 32) -> (19.9606, 32)
  line L5 (19.9606, 32) -> (19.9606, 0)
  line L6 (19.9606, 0) -> (14.9606, 0)
  line L7 (14.9606, 0) -> (14.9606, 32)
  line L8 (-22.9604, 7.079) -> (22, 7.079)
  line L9 (22, 7.079) -> (22, 2.079)
  line L10 (22, 2.079) -> (-22.9604, 2.079)
  line L11 (-22.9604, 2.079) -> (-22.9604, 7.079)
  dimension "d35" = 14.079
  dimension "d36" = 5
  dimension "d37" = 7.079
  constraint horizontal L4
  constraint vertical L5
  constraint horizontal L6
  constraint vertical L7
  constraint coincident L0 L5.end
  constraint horizontal L8
  constraint vertical L9
  constraint horizontal L10
  constraint vertical L11
  constraint coincident L3 L8.start
  measures "d35" distance of L1 L7
  measures "d36" distance of L8.start L10.end
  measures "d37" distance of L0 L8
extrude "Extrude6" add sketch "Sketch7" along normal blind 25 contours L3 L7 L8 L10 L11 | L5 L7 L8 L10 | L4 L5 L7 L8
extrude "Extrude7" add 1 faces at (5.6536, -50.2771, 2.079) along direction (0, 0, -1) blind 2.079
chamfer "Chamfer1" distance 20 angle 45 1 edges at (29.0396, 18.0562, 26.5) tangent chain off
chamfer "Chamfer2" distance 5 angle 45 1 edges at (29.0396, -41.9438, 26.5) tangent chain off
chamfer "Chamfer3" distance 10 angle 45 1 edges at (-22.9604, 18.0562, 26.5) tangent chain off
sketch "Sketch8" plane through (0, 0, 0) normal (0, 0, -1) x (1, 0, 0)
  line L0 (-22.9604, -8.0562) -> (-12.9604, -18.0562)
  line L1 (-12.9604, -18.0562) -> (9.0396, -18.0562)
  line L2 (9.0396, -18.0562) -> (29.0396, 1.9438)
  line L3 (29.0396, 1.9438) -> (29.0396, 36.9438)
  line L4 (29.0396, 36.9438) -> (24.0396, 41.9438)
  line L5 (24.0396, 41.9438) -> (19.9606, 41.9438)
  line L6 (19.9606, 41.9438) -> (19.9606, 66.9438)
  line L7 (19.9606, 66.9438) -> (-22.9604, 66.9438)
  line L8 (-22.9604, 66.9438) -> (-22.9604, -8.0562)
  circle A0 centre (17.0396, 26.9438) radius 7.5
  circle A1 centre (-2.9604, -3.0562) radius 7.5
  circle A2 centre (8.9896, 8.8938) radius 5
  circle A3 centre (-1.0604, 16.5438) radius 4.5
  dimension "d45" = 9
  dimension "d46" = 21.9
  dimension "d47" = 34.6
  measures "d45" diameter of A3
  measures "d46" distance of L8 A3.centre
  measures "d47" distance of L1 A3.centre
extrude "Extrude8" cut sketch "Sketch8" against normal blind 95 contours A3
sketch "Sketch9" plane through (0, 0, 0) normal (0, 0, -1) x (1, 0, 0)
  circle A0 centre (-1.0604, 16.5438) radius 4.5
  line L0 (-22.9604, -8.0562) -> (-12.9604, -18.0562)
  line L1 (-12.9604, -18.0562) -> (9.0396, -18.0562)
  line L2 (9.0396, -18.0562) -> (29.0396, 1.9438)
  line L3 (29.0396, 1.9438) -> (29.0396, 36.9438)
  line L4 (29.0396, 36.9438) -> (24.0396, 41.9438)
  line L5 (24.0396, 41.9438) -> (19.9606, 41.9438)
  line L6 (19.9606, 41.9438) -> (19.9606, 66.9438)
  line L7 (19.9606, 66.9438) -> (-22.9604, 66.9438)
  line L8 (-22.9604, 66.9438) -> (-22.9604, -8.0562)
  circle A1 centre (17.0396, 26.9438) radius 7.5
  circle A2 centre (-2.9604, -3.0562) radius 7.5
  circle A3 centre (8.9896, 8.8938) radius 5
  circle A4 centre (8.9896, 8.8938) radius 5
  constraint concentric A3 A4
extrude "Extrude9" add sketch "Sketch9" against normal blind 53 contours A3 A4
sketch "Sketch10" plane through (0, 0, 53) normal (0, 0, 1) x (-1, 0, 0)
  circle A0 centre (1.0604, 16.5438) radius 4.5
  line L0 (12.9604, -18.0562) -> (22.9604, -8.0562)
  line L1 (22.9604, -8.0562) -> (22.9604, 41.9438)
  line L2 (22.9604, 41.9438) -> (-24.0396, 41.9438)
  line L3 (-24.0396, 41.9438) -> (-29.0396, 36.9438)
  line L4 (-29.0396, 36.9438) -> (-29.0396, 1.9438)
  line L5 (-29.0396, 1.9438) -> (-9.0396, -18.0562)
  line L6 (-9.0396, -18.0562) -> (12.9604, -18.0562)
  circle A1 centre (2.9604, -3.0562) radius 7.5
  circle A2 centre (-17.0396, 26.9438) radius 7.5
  circle A3 centre (2.9604, -3.0562) radius 9
  circle A4 centre (2.9604, -3.0562) radius 10
  circle A5 centre (1.0604, 16.5438) radius 5.5
  circle A6 centre (1.0604, 16.5438) radius 6.5
  circle A7 centre (-17.0396, 26.9438) radius 8
  circle A8 centre (-17.0396, 26.9438) radius 9
  arc A9 (7.5187, 17.2787) -> (12.688, -0.7381) centre (63.8353, 23.6868) ccw
  arc A10 (6.7389, 13.3808) -> (9.3534, 4.6333) centre (64.2522, 25.8064) ccw
  arc A11 (-6.7672, -0.7381) -> (-5.4097, 15.9212) centre (-52.5947, 11.3811) ccw
  arc A12 (-5.044, 2.938) -> (-4.0604, 12.5403) centre (-52.7725, 12.6784) ccw
  arc A13 (-10.2008, 32.7944) -> (1.8027, 23.0012) centre (13.3649, 49.4258) ccw
  arc A14 (-8.3422, 29.258) -> (0.3181, 23.0012) centre (12.8801, 49.511) ccw
  arc A15 (-4.2993, 12.8664) -> (-17.0567, 17.9438) centre (-17.0922, -0.7109) ccw
  arc A16 (-5.3484, 15.4587) -> (-13.4931, 18.672) centre (-16.3605, -0.5248) ccw
  dimension "d52" = 18
  dimension "d53" = 20
  dimension "d54" = 11
  dimension "d55" = 13
  dimension "d56" = 16
  dimension "d57" = 18
  constraint concentric A1 A3
  constraint concentric A1 A4
  constraint concentric A0 A5
  constraint concentric A5 A6
  constraint concentric A2 A7
  constraint concentric A7 A8
  constraint tangent A6 A9
  constraint coincident A6 A9.start
  constraint coincident A4 A9.end
  constraint tangent A9 A10
  constraint coincident A6 A10.start
  constraint coincident A4 A10.end
  constraint tangent A6 A11
  constraint coincident A6 A11.end
  constraint coincident A4 A11.start
  constraint tangent A11 A12
  constraint coincident A6 A12.end
  constraint coincident A4 A12.start
  constraint coincident A8 A13.start
  constraint coincident A6 A13.end
  constraint tangent A13 A14
  constraint coincident A8 A14.start
  constraint coincident A6 A14.end
  constraint tangent A8 A15
  constraint coincident A8 A15.end
  constraint coincident A6 A15.start
  constraint tangent A15 A16
  constraint coincident A8 A16.end
  constraint coincident A6 A16.start
  measures "d52" diameter of A3
  measures "d53" diameter of A4
  measures "d54" diameter of A5
  measures "d55" diameter of A6
  measures "d56" diameter of A7
  measures "d57" diameter of A8
extrude "Extrude10" cut sketch "Sketch10" against normal blind 0.2 contours A4 A9 A11 | A4 A6 A9 A10 | A4 A6 A11 A12 A15 | A6 | A8 A11 A15 A16 | A6 A11 A15 A16 | A6 A8 A13 A14 | A8 A13 picked at (-18.9638, 18.5103)
extrude "Extrude11" cut 1 faces at (14.9606, -58.6104, 15.386) along direction (1, 0, 0) blind 3
sketch "Sketch11" plane through (0, 0, 53) normal (0, 0, 1) x (-1, 0, 0)
  line L0 (12.9604, -18.0562) -> (22.9604, -8.0562)
  line L1 (22.9604, -8.0562) -> (22.9604, 41.9438)
  line L2 (22.9604, 41.9438) -> (-24.0396, 41.9438)
  line L3 (-24.0396, 41.9438) -> (-29.0396, 36.9438)
  line L4 (-29.0396, 36.9438) -> (-29.0396, 1.9438)
  line L5 (-29.0396, 1.9438) -> (-9.0396, -18.0562)
  line L6 (-9.0396, -18.0562) -> (12.9604, -18.0562)
  arc A0 (7.5187, 17.2787) -> (12.688, -0.7381) centre (63.8353, 23.6868) ccw
  arc A1 (-6.7672, -0.7381) -> (12.688, -0.7381) centre (2.9604, -3.0562) ccw
  arc A2 (-6.7672, -0.7381) -> (-5.2487, 13.7019) centre (-52.5947, 11.3811) ccw
  arc A3 (-5.2487, 13.7019) -> (-17.0567, 17.9438) centre (-17.0922, -0.7109) ccw
  arc A4 (-10.2008, 32.7944) -> (-17.0567, 17.9438) centre (-17.0396, 26.9438) ccw
  arc A5 (-10.2008, 32.7944) -> (1.8027, 23.0012) centre (13.3649, 49.4258) ccw
  arc A6 (7.5187, 17.2787) -> (1.8027, 23.0012) centre (1.0604, 16.5438) ccw
sketch "Sketch12" plane through (0, 0, 0) normal (0, 0, -1) x (1, 0, 0)
  circle A0 centre (-1.0604, 16.5438) radius 4.5
  line L0 (-22.9604, -8.0562) -> (-12.9604, -18.0562)
  line L1 (-12.9604, -18.0562) -> (9.0396, -18.0562)
  line L2 (9.0396, -18.0562) -> (29.0396, 1.9438)
  line L3 (29.0396, 1.9438) -> (29.0396, 36.9438)
  line L4 (29.0396, 36.9438) -> (24.0396, 41.9438)
  line L5 (24.0396, 41.9438) -> (19.9606, 41.9438)
  line L6 (19.9606, 41.9438) -> (19.9606, 66.9438)
  line L7 (19.9606, 66.9438) -> (-22.9604, 66.9438)
  line L8 (-22.9604, 66.9438) -> (-22.9604, -8.0562)
  circle A1 centre (17.0396, 26.9438) radius 7.5
  circle A2 centre (-2.9604, -3.0562) radius 7.5
sketch "Sketch13" plane through (0, -41.9438, 0) normal (0, -1, 0) x (1, 0, 0)
  line L0 (24.0396, 0) -> (24.0396, 53)
  line L1 (24.0396, 53) -> (-22.9604, 53)
  line L2 (-22.9604, 53) -> (-22.9604, 7.079)
  line L3 (-22.9604, 7.079) -> (17.9606, 7.079)
  line L4 (17.9606, 7.079) -> (17.9606, 32)
  line L5 (17.9606, 32) -> (19.9606, 32)
  line L6 (19.9606, 32) -> (19.9606, 0)
  line L7 (19.9606, 0) -> (24.0396, 0)
  circle A0 centre (-8.6132, 28.3474) radius 11
  line L8 (17.9606, 7.079) -> (-22.9604, 7.079)
  line L9 (-22.9604, 7.079) -> (-22.9604, 15.079)
  line L10 (-22.9604, 15.079) -> (17.9606, 15.079)
  line L11 (17.9606, 15.079) -> (17.9606, 7.079)
  dimension "d62" = 8
  constraint horizontal L8
  constraint vertical L9
  constraint horizontal L10
  constraint vertical L11
  constraint coincident L3.end L4.start
  measures "d62" distance of L3.end L10.end
extrude "Extrude12" cut sketch "Sketch13" against normal blind 6 contours L2 L3 L4 L8 L9 L10 L11
sketch "Sketch14" plane through (0, 0, 0) normal (0, 0, -1) x (1, 0, 0)
  circle A0 centre (-9.9604, 38.9438) radius 1.5
  circle A1 centre (5.0396, 38.9438) radius 1.5
  line L0 (-22.9604, 66.9438) -> (-22.9604, -8.0562)
  line L1 (19.9606, 66.9438) -> (-22.9604, 66.9438)
  dimension "d65" = 3
  dimension "d66" = 3
  dimension "d67" = 13
  dimension "d68" = 15
  dimension "d69" = 28
  dimension "d70" = 28
  measures "d65" diameter of A0
  measures "d66" diameter of A1
  measures "d67" distance of A0.centre L0
  measures "d68" horizontal distance of A0.centre A1.centre
  measures "d69" distance of A0.centre L1
  measures "d70" distance of A1.centre L1
sketch "Sketch15" plane through (-22.9604, 0, 0) normal (-1, 0, 0) x (0, -1, 0)
  line L0 (35.9438, 15.079) -> (41.9438, 15.079)
  line L1 (41.9438, 15.079) -> (41.9438, 53)
  line L2 (41.9438, 53) -> (-8.0562, 53)
  line L3 (-8.0562, 53) -> (-8.0562, 0)
  line L4 (-8.0562, 0) -> (66.9438, 0)
  line L5 (66.9438, 0) -> (66.9438, 7.079)
  line L6 (66.9438, 7.079) -> (35.9438, 7.079)
  line L7 (35.9438, 7.079) -> (35.9438, 15.079)
  circle A0 centre (26.9438, 13) radius 4
  circle A1 centre (26.9438, 43) radius 4
  line L8 (37.224, 32) -> (37.224, 23)
  line L9 (37.224, 23) -> (21, 23)
  line L10 (21, 23) -> (21, 32)
  line L11 (21, 32) -> (37.224, 32)
  circle A2 centre (35.9438, 11.079) radius 2.9241
  constraint midpoint L7 A2.centre
extrude "Extrude13" cut sketch "Sketch15" against normal blind 41 contours L7 A2 picked at (34.9718, 11.1518)
extrude "Extrude14" cut sketch "Sketch14" against normal blind 17
equation "d15 = 48 mm + 5 mm"
equation "d46 = 17.9 mm + 4 mm"
equation "d47 = 30.6 mm + 4 mm"
